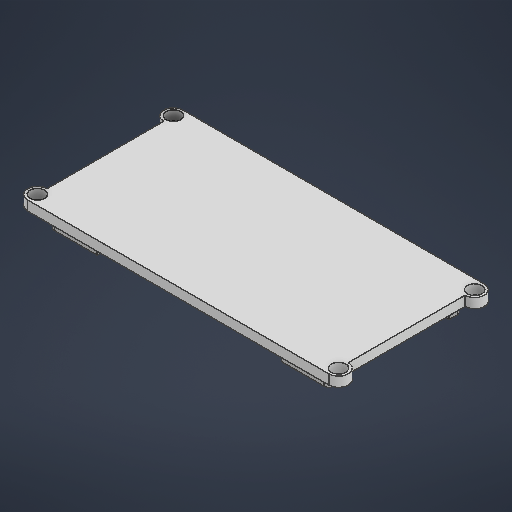
# Autodesk Inventor part: COVER
Saved by Autodesk Inventor 2027.1 (Build 311270010, 270A)
## iProperties
Created: 2026-09-25
Part Number: COVER
Material: 일반
Document SubType Name: Modeling
Designer: work
Density: 1 g/cm^3
Appearance: 기본값
Author: work
Autodesk Inventor part; units mm, degrees
ref_plane "YZ Plane" through (0, 0, 0) normal (1, 0, 0) x (0, 1, 0)
ref_plane "XZ Plane" through (0, 0, 0) normal (0, 1, 0) x (-1, 0, 0)
ref_plane "XY Plane" through (0, 0, 0) normal (0, 0, 1) x (1, 0, 0)
sketch "스케치1" plane through (0, 0, 0) normal (0, 1, 0) x (-1, 0, 0)
  line L0 (0, 0) -> (58, 0)
  line L1 (58, 0) -> (58, -28)
  line L2 (58, -28) -> (0, -28)
  line L3 (0, -28) -> (0, 0)
  line L4 (-2, -30) -> (60, -30)
  line L5 (60, -30) -> (60, 2)
  line L6 (60, 2) -> (-2, 2)
  line L7 (-2, 2) -> (-2, -30)
  line L8 (0, -3.5) -> (-2, -3.5)
  line L9 (-2, -3.5) -> (-2, -24.5)
  line L10 (-2, -24.5) -> (0, -24.5)
  line L11 (0, -24.5) -> (0, -3.5)
  line L12 (58, -5) -> (60, -5)
  line L13 (60, -5) -> (60, -23)
  line L14 (60, -23) -> (58, -23)
  line L15 (58, -23) -> (58, -5)
  circle A0 centre (60, 0) radius 1.1
  line L16 (58, -14) -> (60, -14) construction
  circle A1 centre (60, 0) radius 2
  circle A2 centre (60, -28) radius 1.1
  circle A3 centre (60, -28) radius 2
  circle A4 centre (-2, 0) radius 1.1
  circle A5 centre (-2, 0) radius 2
  circle A6 centre (-2, -28) radius 1.1
  circle A7 centre (-2, -28) radius 2
  line L17 (58, 0) -> (48, 0)
  line L18 (48, 0) -> (48, -3)
  line L19 (48, -3) -> (58, -3)
  line L20 (58, -3) -> (58, 0)
  line L21 (48, -28) -> (48, -25)
  line L22 (48, -25) -> (58, -25)
  line L23 (29, -30) -> (29, 2) construction
  line L24 (10, 0) -> (10, -3)
  line L25 (10, -3) -> (0, -3)
  line L26 (10, -25) -> (0, -25)
  line L27 (10, -28) -> (10, -25)
  point P0 (0, -14)
  point P1 (-2, -14)
  point P2 (59, -23)
  point P3 (59, -5)
  point P4 (60, -2)
  point P5 (-2, -2)
  point P6 (-2, -26)
  point P7 (60, -26)
  dimension "d0" = 58
  dimension "d1" = 28
  dimension "d2" = 2
  dimension "d3" = 21
  dimension "d4" = 18
  dimension "d5" = 2.2
  dimension "d6" = 2.2
  dimension "d7" = 10
  dimension "d8" = 3
  constraints: 56 end point, 13 symmetric about line, 12 midpoint, 10 parallel, 6 centre point, 5 horizontal, 5 perpendicular, 4 coincident, 2 horizontal alignment, 2 point on line, 13 other
  measures "d0" distance of L1.end L2.end
  measures "d1" distance of L0.end L1.end
  measures "d2" distance between parallel lines of L2 L4
  measures "d3" distance of L8.end L9.end
  measures "d4" distance of point (59, -23) point (59, -5)
  measures "d5" diameter of A0
  measures "d6" diameter of A4
  measures "d7" distance of L19.end L18.end
  measures "d8" distance of L18.end L17.end
extrude "돌출1" add sketch "스케치1" along normal blind 2 contours A5 L6 A1 L0 | L0 L24 L25 L3 | A5 L7 A4 | L3 L8 L7 A5 | L0 L18 L19 L1 L22 L21 L2 L27 L26 L3 L25 L24 | L7 A4 A5 | L0 L1 L19 L18 | L3 L10 L7 L8 | A1 L5 A0 | L5 A0 A1 | A1 L5 L12 L1 | L3 A7 L7 L10 | L26 L27 L2 L3 | A7 L7 A6 | L7 A6 A7 | L12 L5 L14 L1 | L2 A3 L4 A7 | L14 L5 A3 L1 | A3 L5 A2 | L5 A2 A3 | L1 L2 L21 L22
extrude "돌출2" add sketch "스케치1" against normal blind 3 contours L0 L24 L25 L3 | L0 L1 L19 L18 | L26 L27 L2 L3 | L1 L2 L21 L22
sketch "스케치2" plane through (0, -3, 0) normal (0, -1, 0) x (1, 0, 0)
  line L0 (0, -25) -> (0, -28) projected
  line L1 (0, -28) -> (-10, -28) projected
  line L2 (-10, -28) -> (-10, -25) projected
  line L3 (-10, -25) -> (0, -25) projected
  line L4 (-58, -28) -> (-58, -25) projected
  line L5 (-58, -25) -> (-48, -25) projected
  line L6 (-48, -25) -> (-48, -28) projected
  line L7 (-48, -28) -> (-58, -28) projected
  line L8 (0, 0) -> (0, -3) projected
  line L9 (0, -3) -> (-10, -3) projected
  line L10 (-10, -3) -> (-10, 0) projected
  line L11 (-10, 0) -> (0, 0) projected
  line L12 (-58, 0) -> (-48, 0) projected
  line L13 (-48, 0) -> (-48, -3) projected
  line L14 (-48, -3) -> (-58, -3) projected
  line L15 (-58, -3) -> (-58, 0) projected
  line L16 (-60, 2) -> (2, 2) projected
  arc A0 (-60, 2) -> (-60, -2) centre (-60, 0) ccw projected
  line L17 (-60, -26) -> (-60, -2) projected
  arc A1 (-60, -26) -> (-60, -30) centre (-60, -28) ccw projected
  line L18 (2, -30) -> (-60, -30) projected
  arc A2 (2, -30) -> (2, -26) centre (2, -28) ccw projected
  line L19 (2, -2) -> (2, -26) projected
  arc A3 (2, -2) -> (2, 2) centre (2, 0) ccw projected
  circle A4 centre (-60, 0) radius 1.1 projected
  circle A5 centre (-60, -28) radius 1.1 projected
  circle A6 centre (2, -28) radius 1.1 projected
  circle A7 centre (2, 0) radius 1.1 projected
  line L20 (-0.3, -27.7) -> (-57.8, -27.7)
  line L21 (-57.8, -27.7) -> (-57.8, -0.3)
  line L22 (-57.8, -0.3) -> (-0.3, -0.3)
  line L23 (-0.3, -0.3) -> (-0.3, -27.7)
  line L24 (-0.3, -27.7) -> (-57.8, -0.3) construction
  line L25 (-57.8, -27.7) -> (-0.3, -0.3) construction
  point P0 (-29.05, -14)
  point P1 (-0.3, -25)
  point P2 (-10, -27.7)
  point P3 (-48, -27.7)
  point P4 (-57.8, -25)
  point P5 (-57.8, -3)
  point P6 (-48, -0.3)
  point P7 (-10, -0.3)
  point P8 (-0.3, -3)
  dimension "d13" = 0.3
  dimension "d14" = 0.2
  dimension "d15" = 0.3
  dimension "d16" = 0.3
  constraints: 12 end point, 2 midpoint, 2 parallel, 1 horizontal, 1 perpendicular
  measures "d13" distance between parallel lines of L12 L22
  measures "d14" distance between parallel lines of L15 L21
  measures "d15" distance between parallel lines of L1 L20
  measures "d16" distance between parallel lines of L0 L23
extrude "돌출3" cut sketch "스케치2" against normal up to surface (3 mm away) contours L0 L1 L2 L20 L23 L3 | L23 L22 L10 L11 L8 L9 | L6 L7 L4 L5 L21 L20 | L22 L21 L14 L15 L12 L13
fillet "모깎기1" radius 1 4 edges at (-0.3, -1.5, -27.7) (-0.3, -1.5, -0.3) (-57.8, -1.5, -27.7) (-57.8, -1.5, -0.3)
extrude "돌출4" add sketch "스케치1" against normal blind 2 contours L12 L5 L14 L1
sketch "스케치3" plane through (0, -2, 0) normal (0, -1, 0) x (1, 0, 0)
  line L0 (-60, -26) -> (-60, -2) projected
  line L1 (-60, -14) -> (-58, -14) construction
  line L2 (-58, -23) -> (-58, -5) projected
  line L3 (-60, -22.7) -> (-58, -22.7)
  line L4 (-60, -23) -> (-58, -23) projected
  line L5 (-60, -5.3) -> (-58, -5.3)
  line L6 (-60, -5) -> (-58, -5)
  point P0 (0, 0)
  point P1 (-59, -22.7)
  dimension "d22" = 0.3
  constraints: 8 end point, 3 midpoint, 3 symmetric about line, 1 horizontal
  measures "d22" distance from line of L4 point (-59, -22.7)
extrude "돌출5" cut sketch "스케치3" against normal blind 2 contours L0 L3 L2 L4 | L0 L6 L2 L5
sketch "스케치4" plane through (0, 2, 0) normal (0, 1, 0) x (1, 0, 0)
  line L0 (-60, -2) -> (2, -2) projected
  line L1 (-14, -2) -> (-14, 30) construction
  line L2 (2, 30) -> (-60, 30) projected
  line L3 (2, 2) -> (2, 26) projected
  circle A0 centre (-14, 11) radius 0.5
  point P0 (0, 0)
  dimension "d25" = 16
  dimension "d26" = 1
  dimension "d27" = 19
  constraints: 3 point on line, 2 end point, 1 centre point, 1 vertical
  measures "d25" distance between parallel lines of L3 L1
  measures "d26" diameter of A0
  measures "d27" distance of L1.end A0.centre
sketch "스케치6" plane through (0, 2, 0) normal (0, 1, 0) x (1, 0, 0)
  line L0 (-60, -2) -> (2, -2) projected
  arc A0 (2, -2) -> (2, 2) centre (2, 0) ccw projected
  line L1 (2, 2) -> (2, 26) projected
  arc A1 (2, 26) -> (2, 30) centre (2, 28) ccw projected
  line L2 (2, 30) -> (-60, 30) projected
  arc A2 (-60, 30) -> (-60, 26) centre (-60, 28) ccw projected
  line L3 (-60, 26) -> (-60, 2) projected
  arc A3 (-60, 2) -> (-60, -2) centre (-60, 0) ccw projected
  circle A4 centre (-60, 0) radius 1.1 projected
  circle A5 centre (-60, 28) radius 1.1 projected
  circle A6 centre (2, 28) radius 1.1 projected
  circle A7 centre (2, 0) radius 1.1 projected
  point P0 (0, 0)
  constraints: 4 coincident
hole "구멍1" at (-60, 2, -28) at (-60, 2, 0) at (2, 2, 0) at (2, 2, -28) direction (0, -1, 0) diameter 3 end through all
fillet "모깎기3" radius 2 8 edges at (-52.9, 0, -3) (-48, 0, -1.65) (-5.15, 0, -3) (-10, 0, -1.65) (-5.15, 0, -25) (-10, 0, -26.35) (-48, 0, -26.35) (-52.9, 0, -25)
